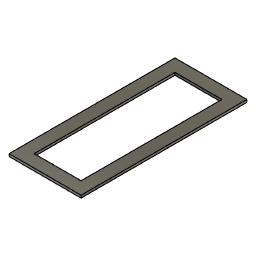
KOGUMA-CHAN (Autodesk Fusion 360 archive; units mm, degrees)
design "1次スカート"
Autodesk Fusion 360 part; units mm, degrees
(part 1 of 2)
sketch "スケッチ1" plane through (0, 0, 0) normal (0, 0, 1) x (1, 0, 0)
  line L0 (-50, 50) -> (-27, 50)
  line L1 (-27, 50) -> (-27, -3)
  line L2 (-27, -3) -> (-50, -3)
  line L3 (-50, -3) -> (-50, 50)
  dimension "d1" = 23
  dimension "d2" = 53
  constraint horizontal L0
  constraint vertical L1
  constraint horizontal L2
  constraint vertical L3
  measures "d1" distance of L0.start L0.end
  measures "d2" distance of L0.start L2.end
sketch "スケッチ2" plane through (0, 0, 0) normal (0, 0, 1) x (1, 0, 0)
extrude "押し出し1" add sketch "スケッチ1" along normal blind 0.8
sketch "スケッチ4" plane through (0, 0, 0.8) normal (0, 0, 1) x (-1, 0, 0)
  line L0 (50, 3) -> (27, 3)
  line L1 (27, 3) -> (27, -50)
  line L2 (27, -50) -> (50, -50)
  line L3 (50, -50) -> (50, 3)
  line L4 (27, 3) -> (50, -50)
  line L5 (27, -50) -> (50, 3)
  line L6 (46, -1) -> (31, -1)
  line L7 (31, -1) -> (31, -46)
  line L8 (31, -46) -> (46, -46)
  line L9 (46, -46) -> (46, -1)
  line L10 (46, -1) -> (31, -46) construction
  line L11 (31, -1) -> (46, -46) construction
  point P0 (38.5, -23.5)
  dimension "d9" = 15
  dimension "d10" = 45
  constraint coincident L0.end L1.start
  constraint coincident L2.end L3.start
  constraint coincident L1.end L2.start
  constraint coincident L0.start L3.end
  constraint horizontal L6
  constraint perpendicular L6 L7
  constraint parallel L6 L8
  constraint parallel L7 L9
  constraint coincident L10 P0
  constraint coincident L11 P0
  constraint midpoint L5 P0
  measures "d9" distance of L7.end L8.end
  measures "d10" distance of L6.end L7.end
extrude "押し出し3" cut sketch "スケッチ4" against normal blind 6 contours L4 L5 L9 | L4 L5 L6 L7 L9 | L4 L5 L7 | L4 L5 L7 L8 L9
sketch "スケッチ3" plane through (0, 0, 0.8) normal (0, 0, 1) x (-1, 0, 0)
  line L0 (50, 3) -> (27, 3)
  line L1 (27, 3) -> (27, -50)
  line L2 (27, -50) -> (50, -50)
  line L3 (50, -50) -> (50, 3)
  line L4 (50, 3) -> (27, -50)
  line L5 (50, -50) -> (27, 3)
  line L6 (26, -53.5) -> (51, -53.5)
  line L7 (51, -53.5) -> (51, 6.5)
  line L8 (51, 6.5) -> (26, 6.5)
  line L9 (26, 6.5) -> (26, -53.5)
  line L10 (26, -53.5) -> (51, 6.5) construction
  line L11 (51, -53.5) -> (26, 6.5) construction
  line L12 (31, -1) -> (46, -1)
  line L13 (46, -1) -> (46, -46)
  line L14 (46, -46) -> (31, -46)
  line L15 (31, -46) -> (31, -1)
  point P0 (38.5, -23.5)
  dimension "d5" = 25
  dimension "d6" = 60
  constraint coincident L0.start L3.end
  constraint coincident L1.end L2.start
  constraint coincident L2.end L3.start
  constraint coincident L0.end L1.start
  constraint horizontal L6
  constraint perpendicular L6 L7
  constraint parallel L6 L8
  constraint parallel L7 L9
  constraint coincident L10 P0
  constraint coincident L11 P0
  constraint midpoint L5 P0
  measures "d5" distance of L7.end L8.end
  measures "d6" distance of L6.end L7.end
extrude "押し出し2" [rolled back] along distance -1 taper angle 0

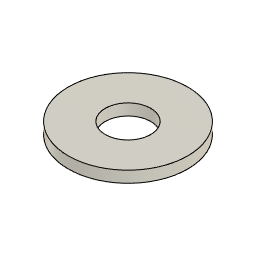
design "歯車M0.3T70"
Autodesk Fusion 360 part; units mm, degrees
sketch "スケッチ1" plane through (0, 0, 0) normal (0, 0, 1) x (1, 0, 0)
  circle A0 centre (0, 0) radius 10.5
  circle A1 centre (0, 0) radius 4
  dimension "d1" = 21
  dimension "d2" = 8
  constraint coincident A0.centre A1.centre
  measures "d1" diameter of A0
  measures "d2" diameter of A1
extrude "押し出し1" add sketch "スケッチ1" along normal blind 2

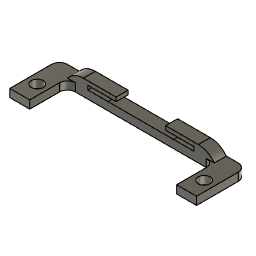
design "モータマウントバック"
Autodesk Fusion 360 part; units mm, degrees
sketch "スケッチ1" plane through (0, 0, 0) normal (0, 0, 1) x (1, 0, 0)
  line L0 (0, 0) -> (-46.8, 0)
  line L1 (-46.8, 0) -> (-46.8, 3)
  line L2 (-46.8, 3) -> (0, 3)
  line L3 (0, 3) -> (0, 0)
  line L4 (-46.8, 3) -> (-23.4, 3)
  line L5 (-46.8, 3) -> (-23.4, 3)
  line L6 (-23.4, 3) -> (-23.4, 0)
  line L7 (0, 0) -> (-5, 0)
  line L8 (-5, 0) -> (-5, -9.445)
  line L9 (-5, -9.445) -> (0, -9.445)
  line L10 (0, -9.445) -> (0, 0)
  line L11 (-5, -9.445) -> (-2.5, -9.445)
  line L12 (-2.5, -9.445) -> (-2.5, -5.045)
  circle A0 centre (-2.5, -5.045) radius 1.5
  line L13 (-41.8, 0) -> (-41.8, -9.445)
  line L14 (-46.8, -9.445) -> (-46.8, 0)
  circle A1 centre (-44.3, -5.045) radius 1.5
  line L15 (-41.8, -9.445) -> (-46.8, -9.445)
  dimension "d1" = 46.8
  dimension "d2" = 3
  dimension "d3" = 5
  dimension "d4" = 9.445
  dimension "d5" = 4.4
  dimension "d6" = 3
  constraint horizontal L0
  constraint vertical L1
  constraint horizontal L2
  constraint vertical L3
  constraint coincident L0.start L3.end
  constraint midpoint L2 L4.end
  constraint midpoint L0 L6.end
  constraint horizontal L7
  constraint vertical L8
  constraint horizontal L9
  constraint vertical L10
  constraint midpoint L9 L11.end
  constraint perpendicular L9 L12
  constraint coincident L12.end A0.centre
  constraint symmetric L6 L0.start L0.end
  constraint symmetric L6 L7.end L13.start
  constraint symmetric L6 L8.end L13.end
  constraint symmetric L6 L9.end L14.start
  constraint symmetric L6 A0 A1
  measures "d1" distance of L0.start L0.end
  measures "d2" distance of L0 L2
  measures "d3" distance of L0.start L7.end
  measures "d4" distance of L0.start L9.end
  measures "d5" distance of L11.end L12.end
  measures "d6" diameter of A0
extrude "押し出し1" add sketch "スケッチ1" along normal blind 2
fillet "フィレット1" radius 2 4 edges at (-41.8, 0, 1) (-5, 0, 1) (0, 3, 1) (-46.8, 3, 1)
sketch "スケッチ2" plane through (0, 0, 2) normal (0, 0, 1) x (-1, 0, 0)
  arc A0 (44.8, -3) -> (46.8, -1) centre (44.8, -1) ccw
  line L0 (46.8, -1) -> (46.8, 9.445)
  line L1 (46.8, 9.445) -> (41.8, 9.445)
  line L2 (41.8, 9.445) -> (41.8, 2)
  arc A1 (39.8, 0) -> (41.8, 2) centre (39.8, 2) ccw
  line L3 (39.8, 0) -> (7, 0)
  arc A2 (5, 2) -> (7, 0) centre (7, 2) ccw
  line L4 (5, 2) -> (5, 9.445)
  line L5 (5, 9.445) -> (0, 9.445)
  line L6 (0, 9.445) -> (0, -1)
  arc A3 (0, -1) -> (2, -3) centre (2, -1) ccw
  line L7 (2, -3) -> (44.8, -3)
  circle A4 centre (44.3, 5.045) radius 1.5
  circle A5 centre (2.5, 5.045) radius 1.5
  line L8 (41.8, 9.445) -> (41.8, -1)
  line L9 (41.8, -1) -> (41.8, 0)
  line L10 (41.8, 0) -> (3.6393, 0)
  line L11 (3.6393, 0) -> (5, 0)
  line L12 (5, 0) -> (41.8, 0)
  line L13 (41.8, 0) -> (41.8, -3)
  line L14 (41.8, -3) -> (5, -3)
  line L15 (5, -3) -> (5, 0)
  constraint coincident L1.end L2.start
  constraint perpendicular L1 L8
  constraint coincident L8 L9.end
  constraint perpendicular L8 L10
  constraint coincident L10 L11.end
  constraint horizontal L12
  constraint vertical L13
  constraint horizontal L14
  constraint vertical L15
  constraint coincident L7 L13.end
extrude "押し出し2" add sketch "スケッチ2" along normal blind 2 contours L3 L7 L8 L9 L10 L12 L13 L14 L15
sketch "スケッチ3" plane through (0, 0, 0) normal (0, -1, 0) x (1, 0, 0)
  line L0 (-7, 0) -> (-7, 2)
  line L1 (-7, 2) -> (-5, 2)
  line L2 (-5, 2) -> (-5, 4)
  line L3 (-5, 4) -> (-41.8, 4)
  line L4 (-41.8, 4) -> (-41.8, 2)
  line L5 (-41.8, 2) -> (-39.8, 2)
  line L6 (-39.8, 2) -> (-39.8, 0)
  line L7 (-39.8, 0) -> (-7, 0)
  line L8 (-39.8, 2) -> (-7, 2)
  line L9 (-39.8, 2) -> (-23.4, 2)
  line L10 (-39.8, 2) -> (-31.6, 2)
  line L11 (-31.6, 2) -> (-31.6, 4)
  line L12 (-7, 2) -> (-23.4, 2)
  line L13 (-7, 2) -> (-15.2, 2)
  line L14 (-15.2, 2) -> (-15.2, 4)
  line L15 (-31.6, 4) -> (-15.2, 4)
  line L16 (-15.2, 4) -> (-15.2, 2)
  line L17 (-15.2, 2) -> (-31.6, 2)
  line L18 (-31.6, 2) -> (-31.6, 4)
  constraint coincident L5.end L6.start
  constraint coincident L0.end L1.start
  constraint midpoint L8 L9.end
  constraint midpoint L9 L10.end
  constraint coincident L3 L11.end
  constraint perpendicular L3 L11
  constraint midpoint L12 L13.end
  constraint coincident L3 L14.end
  constraint perpendicular L3 L14
  constraint horizontal L15
  constraint vertical L16
  constraint horizontal L17
  constraint vertical L18
extrude "押し出し3" cut sketch "スケッチ3" against normal blind 3 contours L3 L8 L9 L11 L12 L14 L15 L16 L17 L18
sketch "スケッチ4" plane through (0, 0, 0) normal (0, -1, 0) x (1, 0, 0)
  line L0 (-31.6, 2) -> (-31.6, 4)
  line L1 (-31.6, 4) -> (-41.8, 4)
  line L2 (-41.8, 4) -> (-41.8, 2)
  line L3 (-41.8, 2) -> (-39.8, 2)
  line L4 (-39.8, 2) -> (-39.8, 0)
  line L5 (-39.8, 0) -> (-7, 0)
  line L6 (-7, 0) -> (-7, 2)
  line L7 (-7, 2) -> (-5, 2)
  line L8 (-5, 2) -> (-5, 4)
  line L9 (-5, 4) -> (-15.2, 4)
  line L10 (-15.2, 4) -> (-15.2, 2)
  line L11 (-15.2, 2) -> (-31.6, 2)
  line L12 (-31.6, 4) -> (-31.6, 3)
  line L13 (-31.6, 3) -> (-36.7, 3)
  line L14 (-36.7, 3) -> (-36.7, 2)
  line L15 (-36.7, 2) -> (-31.6, 2)
  line L16 (-15.2, 4) -> (-15.2, 3)
  line L17 (-15.2, 3) -> (-10.1, 3)
  line L18 (-10.1, 3) -> (-10.1, 2)
  line L19 (-10.1, 2) -> (-15.2, 2)
  line L20 (-15.2, 3) -> (-15.2, 2)
  line L21 (-31.6, 3) -> (-31.6, 2)
  constraint coincident L0.end L1.start
  constraint midpoint L0 L12.end
  constraint perpendicular L12 L13
  constraint perpendicular L1 L14
  constraint coincident L0.start L11.end
  constraint coincident L9.end L10.start
  constraint midpoint L10 L16.end
  constraint perpendicular L10 L17
  constraint perpendicular L17 L18
  constraint coincident L10.end L11.start
extrude "押し出し4" cut sketch "スケッチ4" against normal blind 4 contours L0 L13 L14 L15 L21 | L10 L17 L18 L19 L20
fillet "フィレット2" radius 5 2 edges at (-41.8, 1.5, 4) (-5, 1.5, 4)
extrude "押し出し5" add 1 faces at (-31.6, 1, 3.3333) along direction (1, 0, 0) blind 2
extrude "押し出し6" add 1 faces at (-15.2, 1, 3.3333) along direction (-1, 0, 0) blind 2
equation "d5 = 2.9 mm + 1.5 mm"

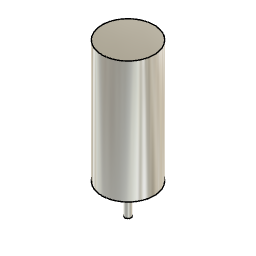
design "吸引モータ"
Autodesk Fusion 360 part; units mm, degrees
sketch "スケッチ1" plane through (0, 0, 0) normal (0, 0, 1) x (1, 0, 0)
  circle A0 centre (0, 0) radius 4.25
  dimension "d1" = 8.5
  constraint coincident A0.centre origin
  measures "d1" diameter of A0
extrude "押し出し1" add sketch "スケッチ1" along normal blind 20
sketch "スケッチ2" plane through (0, 0, 0) normal (0, 0, -1) x (1, 0, 0)
  circle A0 centre (0, 0) radius 4.25
  circle A1 centre (0, 0) radius 0.5
  dimension "d4" = 1
  constraint coincident A0.centre A1.centre
  measures "d4" diameter of A1
extrude "押し出し2" add sketch "スケッチ2" along normal blind 5 contours A1

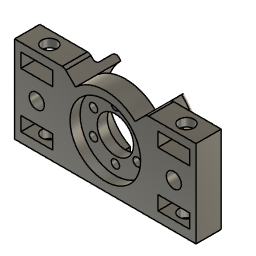
design "モーターマウント"
Autodesk Fusion 360 part; units mm, degrees
sketch "スケッチ1" plane through (0, 0, 0) normal (0, 1, 0) x (1, 0, 0)
  circle A0 centre (0, 0) radius 8.6
  line L0 (57.1333, 8.5) -> (67.1333, 8.5) construction
  circle A1 centre (0, 0) radius 3.6
  circle A2 centre (-13.6, 0) radius 10.5 construction
  circle A3 centre (13.6, 0) radius 10.5 construction
  circle A4 centre (0, 0) radius 5
  circle A5 centre (-0.0024, -5) radius 0.825
  circle A6 centre (4.3289, -2.502) radius 0.825
  circle A7 centre (4.3313, 2.498) radius 0.825
  circle A8 centre (0.0024, 5) radius 0.825
  circle A9 centre (-4.3289, 2.502) radius 0.825
  circle A10 centre (-4.3313, -2.498) radius 0.825
  circle A11 centre (-13.6, 0) radius 12.25 construction
  circle A12 centre (-13.6, 0) radius 1.5
  circle A13 centre (13.6, 0) radius 1.5
  line L1 (-13.6, 0) -> (-13.6, 12.25)
  line L2 (-13.6, 12.25) -> (-3.6, 12.25)
  line L3 (-3.6, 12.25) -> (-3.6, 9.75)
  line L4 (-3.6, 9.75) -> (-3.6, 8.75)
  line L5 (-3.6, 8.75) -> (27, 8.75)
  line L6 (0, 0) -> (0, 8.75)
  line L7 (0, 8.75) -> (18, 8.75)
  line L8 (18, 8.75) -> (18, -6.25)
  line L9 (18, -6.25) -> (0, -6.25)
  line L10 (0, -6.25) -> (0, 8.75)
  line L11 (-18, -6.25) -> (0, -6.25)
  line L12 (-18, 8.75) -> (-18, -6.25)
  line L13 (0, 8.75) -> (-18, 8.75)
  line L14 (18, -6.25) -> (-18, -6.25)
  line L15 (-18, -6.25) -> (-18, -8.4837)
  line L16 (-18, -8.4837) -> (18, -8.4837)
  line L17 (18, -8.4837) -> (18, -6.25)
  line L18 (18, -8.4837) -> (9, -8.4837)
  line L19 (18, -8.4837) -> (8, -8.4837)
  line L20 (5.9074, -6.25) -> (8.1411, -8.4837)
  line L21 (5.9074, -6.25) -> (8.9428, -6.25) construction
  line L22 (-5.9074, -6.25) -> (-8.1574, -8.5)
  dimension "d1" = 17.2
  dimension "d2" = 8.5
  dimension "d3" = 7.2
  dimension "d4" = 21
  dimension "d5" = 13.6
  dimension "d7" = 21
  dimension "d8" = 13.6
  dimension "d9" = 8.5
  dimension "d10" = 8.5
  dimension "d16" = 10
  dimension "d17" = 1.65
  dimension "d19" = 360
  dimension "d20" = 24.5
  dimension "d21" = 3
  dimension "d22" = 3
  dimension "d25" = 2.5
  dimension "d26" = 1
  dimension "d27" = 18
  dimension "d28" = 15
  dimension "d48" = 45
  dimension "d49" = 90
  dimension "d50" = 3.182
  constraint coincident A0.centre A1.centre
  constraint horizontal L0
  constraint concentric A0 A1
  constraint concentric A0 A4
  constraint coincident A4 A5.centre
  constraint concentric A2 A11
  constraint concentric A2 A12
  constraint concentric A3 A13
  constraint coincident A2.centre A11.centre
  constraint coincident A11 L1.end
  constraint vertical L1
  constraint tangent A11 L2
  constraint equal L0 L2
  constraint perpendicular L2 L3
  constraint parallel L3 L4
  constraint perpendicular L4 L5
  constraint coincident L5 L6.end
  constraint perpendicular L5 L6
  constraint horizontal L7
  constraint vertical L8
  constraint horizontal L9
  constraint vertical L10
  constraint symmetric L6.end L10 L7.start
  constraint symmetric L7.end L10 L12.start
  constraint symmetric L8.end L10 L11.start
  constraint symmetric L9.end L10 L11.end
  constraint horizontal L14
  constraint vertical L15
  constraint horizontal L16
  constraint vertical L17
  constraint coincident L16 L18.end
  constraint perpendicular L17 L18
  constraint coincident L16 L19.end
  constraint horizontal L21
  constraint coincident A0 L20.start
  constraint coincident L14 L20.start
  constraint coincident L16 L20.end
  constraint coincident A0 L22.start
  constraint coincident L14 L22.start
  measures "d1" diameter of A0
  measures "d2" distance of A0.centre L0
  measures "d3" diameter of A1
  measures "d4" diameter of A2
  measures "d5" distance of A0.centre A2.centre
  measures "d7" diameter of A3
  measures "d8" distance of A0.centre A3.centre
  measures "d9" distance of L0 A3.centre
  measures "d10" distance of L0 A2.centre
  measures "d16" diameter of A4
  measures "d17" diameter of A5
  measures "d20" diameter of A11
  measures "d21" diameter of A12
  measures "d22" diameter of A13
  measures "d25" distance of L2.end L3.end
  measures "d26" distance of L3.end L4.end
  measures "d27" distance of L6.end L7.end
  measures "d28" distance of L6.end L9.end
  measures "d48" angle of L20 L21
  measures "d49" angle of L20 L22
  measures "d50" distance of L22.start L22.end
extrude "押し出し1" add sketch "スケッチ1" against normal blind 5 contours A0 A4 A5 A6 A7 A8 L6 L9 L10 L14 | A0 L5 L6 L7 L8 L9 L10 L14 | A0 L9 L11 L14 L16 | L9 L14 L16 L17 L18 L19 L20 | A0 L16 | A0 A4 A5 A8 A9 A10 L6 L10 L11 L14 | A0 L5 L6 L10 L11 L12 L13 L14 | L11 L14 L15 L16 L22 | A1 A4 A5 A8 A9 A10 L6 L10 | A1 A4 A5 A6 A7 A8 L6 L10
sketch "スケッチ2" plane through (0, 0, -8.75) normal (0, 0, -1) x (1, 0, 0)
  line L0 (-18, 0) -> (18, 0)
  line L1 (18, 0) -> (18, 5)
  line L2 (18, 5) -> (-18, 5)
  line L3 (-18, 5) -> (-18, 0)
  line L4 (-18, 5) -> (-13.6, 5)
  line L5 (-13.6, 5) -> (-13.6, 0)
  line L6 (-13.6, 5) -> (-13.6, 2.5)
  line L7 (-18, 2.5) -> (-13.6, 2.5)
  circle A0 centre (-13.6, 2.5) radius 1.05
  line L8 (0, 0) -> (0, 5)
  circle A1 centre (13.6, 2.5) radius 1.05
  dimension "d31" = 4.4
  dimension "d33" = 2.1
  constraint coincident L2.end L3.start
  constraint perpendicular L3 L4
  constraint coincident L0 L5.end
  constraint perpendicular L0 L5
  constraint midpoint L5 L6.end
  constraint midpoint L3 L7.start
  constraint coincident L6.end L7.end
  constraint coincident L8.start origin
  constraint midpoint L2 L8.end
  constraint symmetric A0 L8 A1
  measures "d31" distance of L2.end L4.end
  measures "d33" diameter of A0
hole "穴1" at (-13.6, -2.5, -8.75) at (13.6, -2.5, -8.75) direction (0, 0, 1) diameter 3 depth 4 tip angle 180
sketch "スケッチ3" plane through (0, -5, 0) normal (0, -1, 0) x (1, 0, 0)
  circle A0 centre (13.6, 0) radius 1.5
  circle A1 centre (-0.0024, 5) radius 0.825
  circle A2 centre (4.3289, 2.502) radius 0.825
  circle A3 centre (4.3313, -2.498) radius 0.825
  circle A4 centre (-4.3313, 2.498) radius 0.825
  circle A5 centre (0.0024, -5) radius 0.825
  circle A6 centre (-4.3289, -2.502) radius 0.825
  circle A7 centre (-13.6, 0) radius 1.5
  line L0 (-18, -8.75) -> (18, -8.75)
  line L1 (18, -8.75) -> (18, 8.4837)
  line L2 (-18, 8.4837) -> (-18, -8.75)
  circle A8 centre (0, 0) radius 7
  line L3 (-8.1411, 8.4837) -> (-18, 8.4837)
  arc A9 (5.9074, 6.25) -> (-5.9074, 6.25) centre (0, 0) ccw
  line L4 (-5.9074, 6.25) -> (-8.1411, 8.4837)
  line L5 (18, 8.4837) -> (8.1411, 8.4837)
  line L6 (8.1411, 8.4837) -> (5.9074, 6.25)
  circle A10 centre (0, 0) radius 3.6
  dimension "d37" = 14
  constraint coincident A8.centre A9.centre
  measures "d37" diameter of A8
extrude "押し出し2" cut sketch "スケッチ3" against normal blind 2 contours A8 | A10
sketch "スケッチ4" plane through (0, 0, 0) normal (0, 1, 0) x (-1, 0, 0)
  circle A0 centre (-13.6, 0) radius 1.5
  circle A1 centre (0.0024, 5) radius 0.825
  circle A2 centre (-4.3289, 2.502) radius 0.825
  circle A3 centre (-4.3313, -2.498) radius 0.825
  circle A4 centre (4.3313, 2.498) radius 0.825
  circle A5 centre (-0.0024, -5) radius 0.825
  circle A6 centre (4.3289, -2.502) radius 0.825
  circle A7 centre (13.6, 0) radius 1.5
  line L0 (-18, -8.75) -> (18, -8.75)
  line L1 (18, -8.75) -> (18, 8.4837)
  line L2 (-18, 8.4837) -> (-18, -8.75)
  circle A8 centre (0, 0) radius 8.6
  line L3 (-8.1411, 8.4837) -> (-18, 8.4837)
  arc A9 (5.9074, 6.25) -> (-5.9074, 6.25) centre (0, 0) ccw
  line L4 (-5.9074, 6.25) -> (-8.1411, 8.4837)
  line L5 (18, 8.4837) -> (8.1411, 8.4837)
  line L6 (8.1411, 8.4837) -> (5.9074, 6.25)
  circle A10 centre (0, 0) radius 3.6
  dimension "d85" = 17.2
  measures "d85" diameter of A8
extrude "押し出し3" cut sketch "スケッチ4" against normal blind 1 contours A8 A9 | A10
sketch "スケッチ5" plane through (0, 0, 0) normal (0, 1, 0) x (-1, 0, 0)
  line L0 (-18, 8.4837) -> (-18, -8.75)
  line L1 (-18, -8.75) -> (18, -8.75)
  line L2 (18, -8.75) -> (18, 8.4837)
  circle A0 centre (13.6, 0) radius 1.5
  circle A1 centre (-13.6, 0) radius 1.5
  line L3 (-13.6, 0) -> (-13.6, 3.3255)
  line L4 (-13.6, 0) -> (-10.72, 1.6628)
  line L5 (-13.6, 0) -> (-9.9931, 0) construction
  line L6 (-13.6, 3.3255) -> (-10.72, 1.6628)
  line L7 (-16.48, 1.6628) -> (-13.6, 3.3255)
  line L8 (-16.48, -1.6627) -> (-16.48, 1.6627)
  line L9 (-13.6, -3.3255) -> (-16.48, -1.6628)
  line L10 (-10.72, -1.6628) -> (-13.6, -3.3255)
  line L11 (-10.72, 1.6627) -> (-10.72, -1.6628)
  line L12 (0, 0) -> (0, 5)
  line L13 (13.6, 3.3255) -> (10.72, 1.6628)
  line L14 (10.72, 1.6627) -> (10.72, -1.6628)
  line L15 (10.72, -1.6628) -> (13.6, -3.3255)
  line L16 (13.6, -3.3255) -> (16.48, -1.6628)
  line L17 (16.48, -1.6627) -> (16.48, 1.6627)
  line L18 (16.48, 1.6628) -> (13.6, 3.3255)
  line L19 (18, 8.4837) -> (8.1411, 8.4837)
  line L20 (-8.1411, 8.4837) -> (-18, 8.4837)
  line L21 (-5.9074, 6.25) -> (-8.1411, 8.4837)
  line L22 (8.1411, 8.4837) -> (5.9074, 6.25)
  arc A2 (-5.9074, 6.25) -> (5.9074, 6.25) centre (0, 0) ccw
  dimension "d42" = 3.3255
  dimension "d43" = 30
  dimension "d45" = 360
  constraint coincident A1.centre L3.start
  constraint vertical L3
  constraint horizontal L5
  constraint equal L3 L4
  constraint vertical L12
  constraint symmetric L3.end L12 L13.start
  constraint symmetric L4.end L12 L13.end
  constraint symmetric L7.start L12 L18.start
  constraint symmetric L8.start L12 L17.start
  constraint symmetric L8.end L12 L17.end
  constraint symmetric L9.start L12 L15.end
  constraint symmetric L9.end L12 L16.end
  constraint symmetric L10.start L12 L14.end
  constraint symmetric L11.start L12 L14.start
  measures "d42" distance of A1.centre L3.end
  measures "d43" angle of L4 L5
extrude "押し出し4" cut sketch "スケッチ5" against normal blind 2.5 contours A1 L3 L4 L7 L8 L9 L10 L11 | A1 L3 L4 L6 | L13 L14 L15 L16 L17 L18
fillet "フィレット1" radius 1 1 edges at (8.1411, -2.5, 8.4837)
fillet "フィレット2" radius 1 1 edges at (-8.1411, -2.5, 8.4837)
sketch "スケッチ6" plane through (0, 0, 0) normal (0, 1, 0) x (1, 0, 0)
sketch "スケッチ7" plane through (0, 0, -8.75) normal (0, 0, -1) x (1, 0, 0)
  circle A0 centre (-13.6, 2.5) radius 1.5
  circle A1 centre (13.6, 2.5) radius 1.5
  line L0 (-18, 0) -> (18, 0)
  line L1 (18, 0) -> (18, 5)
  line L2 (18, 5) -> (-18, 5)
  line L3 (-18, 5) -> (-18, 0)
  line L4 (18, 2.5) -> (9, 2.5)
  line L5 (9, 2.5) -> (9, 2)
  line L6 (9, 2) -> (4, 2)
  line L7 (4, 2) -> (4, 3)
  line L8 (4, 3) -> (9, 3)
  line L9 (9, 3) -> (9, 2.5)
  line L10 (18, 2.5) -> (13.6, 2.5)
  line L11 (18, 2.5) -> (15.8, 2.5)
  line L12 (15.8, 2.5) -> (15.8, 4)
  line L13 (15.8, 4) -> (16.8, 4)
  line L14 (16.8, 4) -> (16.8, 1)
  line L15 (16.8, 1) -> (15.8, 1)
  line L16 (15.8, 1) -> (15.8, 2.5)
  line L17 (0, 0) -> (0, 5)
  line L18 (-16.8, 1) -> (-15.8, 1)
  line L19 (-16.8, 4) -> (-16.8, 1)
  line L20 (-15.8, 1) -> (-15.8, 2.5)
  line L21 (-15.8, 2.5) -> (-15.8, 4)
  line L22 (-15.8, 4) -> (-16.8, 4)
  line L23 (-9, 2.5) -> (-9, 2)
  line L24 (-9, 3) -> (-9, 2.5)
  line L25 (-4, 3) -> (-9, 3)
  line L26 (-9, 2) -> (-4, 2)
  line L27 (-4, 2) -> (-4, 3)
  dimension "d55" = 1
  dimension "d56" = 90
  dimension "d57" = 3
  dimension "d58" = 1
  dimension "d59" = 0.5
  dimension "d60" = 0.5
  dimension "d61" = 5
  constraint midpoint L1 L4.start
  constraint perpendicular L1 L4
  constraint perpendicular L4 L5
  constraint perpendicular L5 L6
  constraint perpendicular L6 L7
  constraint perpendicular L7 L8
  constraint perpendicular L4 L9
  constraint coincident A1.centre L10.end
  constraint midpoint L10 L11.end
  constraint perpendicular L4 L12
  constraint perpendicular L11 L14
  constraint perpendicular L14 L15
  constraint coincident L17.start origin
  constraint midpoint L2 L17.end
  constraint symmetric L4.end L17 L23.start
  constraint symmetric L5.end L17 L23.end
  constraint symmetric L6.end L17 L26.end
  constraint symmetric L7.end L17 L25.start
  constraint symmetric L8.end L17 L24.start
  constraint symmetric L11.end L17 L20.end
  constraint symmetric L12.end L17 L21.end
  constraint symmetric L13.end L17 L19.start
  constraint symmetric L14.end L17 L18.start
  constraint symmetric L15.end L17 L18.end
  measures "d55" distance of L12.end L13.end
  measures "d56" angle of L12 L13
  measures "d57" distance of L13.end L14.end
  measures "d58" distance of L14.end L15.end
  measures "d59" distance of L4.end L5.end
  measures "d60" distance of L4.end L8.end
  measures "d61" distance of L7.end L8.end
sketch "スケッチ8" plane through (0, 0, 0) normal (0, 1, 0) x (-1, 0, 0)
  line L0 (-16.48, 1.6627) -> (-13.6, 3.3255)
  line L1 (-13.6, 3.3255) -> (-10.72, 1.6627)
  line L2 (-10.72, 1.6627) -> (-10.72, -1.6628)
  line L3 (-10.72, -1.6628) -> (-13.6, -3.3255)
  line L4 (-13.6, -3.3255) -> (-16.48, -1.6628)
  line L5 (-16.48, -1.6628) -> (-16.48, 1.6627)
  line L6 (10.72, 1.6627) -> (13.6, 3.3255)
  line L7 (13.6, 3.3255) -> (16.48, 1.6628)
  line L8 (16.48, 1.6628) -> (16.48, -1.6627)
  line L9 (16.48, -1.6627) -> (13.6, -3.3255)
  line L10 (13.6, -3.3255) -> (10.72, -1.6628)
  line L11 (10.72, -1.6628) -> (10.72, 1.6627)
  arc A0 (8.5553, 8.4837) -> (7.8482, 8.1908) centre (8.5553, 7.4837) ccw
  line L12 (7.8482, 8.1908) -> (5.9074, 6.25)
  line L13 (-5.9074, 6.25) -> (-7.8482, 8.1908)
  arc A1 (-7.8482, 8.1908) -> (-8.5553, 8.4837) centre (-8.5553, 7.4837) ccw
  line L14 (-8.5553, 8.4837) -> (-18, 8.4837)
  line L15 (-18, 8.4837) -> (-18, -8.75)
  line L16 (-18, -8.75) -> (18, -8.75)
  line L17 (18, -8.75) -> (18, 8.4837)
  line L18 (18, 8.4837) -> (8.5553, 8.4837)
  arc A2 (-5.9074, 6.25) -> (5.9074, 6.25) centre (0, 0) ccw
sketch "スケッチ9" plane through (0, -5, 0) normal (0, -1, 0) x (1, 0, 0)
  arc A0 (-7.8482, 8.1908) -> (-8.5553, 8.4837) centre (-8.5553, 7.4837) ccw
  line L0 (-8.5553, 8.4837) -> (-18, 8.4837)
  line L1 (-18, 8.4837) -> (-18, -8.75)
  line L2 (-18, -8.75) -> (18, -8.75)
  line L3 (18, -8.75) -> (18, 8.4837)
  line L4 (18, 8.4837) -> (8.5553, 8.4837)
  arc A1 (8.5553, 8.4837) -> (7.8482, 8.1908) centre (8.5553, 7.4837) ccw
  line L5 (7.8482, 8.1908) -> (5.9074, 6.25)
  arc A2 (5.9074, 6.25) -> (-5.9074, 6.25) centre (0, 0) ccw
  line L6 (-5.9074, 6.25) -> (-7.8482, 8.1908)
  circle A3 centre (0, 0) radius 7
  circle A4 centre (13.6, 0) radius 1.5
  circle A5 centre (-13.6, 0) radius 1.5
  line L7 (-13.6, 0) -> (-13.6, -8.75)
  line L8 (-13.6, -8.75) -> (-13.6, -5.75)
  line L9 (-13.6, -5.75) -> (-13.6, -6.85)
  line L10 (-13.6, -6.85) -> (-10.45, -6.85)
  line L11 (-10.45, -6.85) -> (-16.75, -6.85)
  line L12 (-16.75, -6.85) -> (-16.75, -4.05)
  line L13 (-16.75, -4.05) -> (-10.45, -4.05)
  line L14 (-10.45, -4.05) -> (-10.45, -6.85)
  line L15 (-13.6, 0) -> (-12.1, 0)
  line L16 (-10.45, 4.05) -> (-10.45, 6.85)
  line L17 (-16.75, 4.05) -> (-10.45, 4.05)
  line L18 (-16.75, 6.85) -> (-16.75, 4.05)
  line L19 (-10.45, 6.85) -> (-16.75, 6.85)
  line L20 (0, 0) -> (0, -1.3503)
  line L21 (16.75, 4.05) -> (10.45, 4.05)
  line L22 (16.75, 6.85) -> (16.75, 4.05)
  line L23 (10.45, 6.85) -> (16.75, 6.85)
  line L24 (10.45, 4.05) -> (10.45, 6.85)
  line L25 (16.75, -4.05) -> (10.45, -4.05)
  line L26 (10.45, -4.05) -> (10.45, -6.85)
  line L27 (16.75, -6.85) -> (16.75, -4.05)
  line L28 (10.45, -6.85) -> (16.75, -6.85)
  dimension "d64" = 3
  dimension "d65" = 1.1
  dimension "d66" = 3.15
  dimension "d67" = 6.3
  dimension "d68" = 2.8
  constraint coincident A5.centre L7.start
  constraint coincident L2 L7.end
  constraint perpendicular L2 L7
  constraint perpendicular L2 L8
  constraint parallel L7 L9
  constraint perpendicular L9 L10
  constraint horizontal L11
  constraint vertical L12
  constraint horizontal L13
  constraint vertical L14
  constraint coincident A5 L15.end
  constraint perpendicular L7 L15
  constraint symmetric L10.end L15 L16.end
  constraint symmetric L11.end L15 L18.start
  constraint symmetric L12.end L15 L17.start
  constraint symmetric L13.end L15 L16.start
  constraint coincident A2.centre A3.centre
  constraint vertical L20
  constraint symmetric L10.end L20 L26.end
  constraint symmetric L11.end L20 L27.start
  constraint symmetric L12.end L20 L25.start
  constraint symmetric L13.end L20 L25.end
  constraint symmetric L16.start L20 L21.end
  constraint symmetric L16.end L20 L23.start
  constraint symmetric L17.start L20 L21.start
  constraint symmetric L18.start L20 L22.start
  measures "d64" distance of L7.end L8.end
  measures "d65" distance of L8.end L9.end
  measures "d66" distance of L9.end L10.end
  measures "d67" distance of L10.end L11.end
  measures "d68" distance of L10.end L13.end
sketch "スケッチ10" plane through (0, -5, 0) normal (0, -1, 0) x (1, 0, 0)
extrude "押し出し6" cut sketch "スケッチ9" against normal blind 6.5 contours L7 L8 L9 L10 L11 L13 L14 | L7 L8 L9 L11 L12 L13 | L16 L17 L18 L19 | L21 L22 L23 L24 | L25 L26 L27 L28
sketch "スケッチ11" plane through (0, 0, 8.4837) normal (0, 0, 1) x (-1, 0, 0)
  line L0 (8.5553, 5) -> (8.5553, 0)
  line L1 (8.5553, 0) -> (18, 0)
  line L2 (18, 0) -> (18, 5)
  line L3 (18, 5) -> (8.5553, 5)
  line L4 (18, 5) -> (18, 2.5)
  line L5 (18, 2.5) -> (13.6, 2.5)
  line L6 (0, 0) -> (0, 5)
  line L7 (-18, 2.5) -> (-13.6, 2.5)
  dimension "d71" = 4.4
  constraint coincident L2.end L3.start
  constraint midpoint L2 L4.end
  constraint perpendicular L2 L5
  constraint coincident L6.start origin
  constraint vertical L6
  constraint symmetric L4.end L6 L7.start
  constraint symmetric L5.end L6 L7.end
  measures "d71" distance of L4.end L5.end
hole "穴2" at (-13.6, -2.5, 8.4837) at (13.6, -2.5, 8.4837) direction (0, 0, -1) diameter 3 depth 3 tip angle 180
sketch "スケッチ12" plane through (0, 0, 0) normal (0, 1, 0) x (-1, 0, 0)
  line L0 (18, -8.75) -> (-18, -8.75)
  line L1 (-18, -8.75) -> (-18, 8.6)
  line L2 (-18, 8.6) -> (18, 8.6)
  line L3 (18, 8.6) -> (18, -8.75)
  circle A0 centre (0, 0) radius 8.6
  circle A1 centre (0, 0) radius 10
  line L4 (-5.9074, 6.25) -> (-964.7442, 965.0868)
  line L5 (-5.9074, 6.25) -> (1350.239, 6.25) construction
  line L6 (0, 0) -> (0, 1.2)
  line L7 (5.9074, 6.25) -> (964.7442, 965.0868)
  line L8 (-4.0393, -8.75) -> (-4.0393, -7.5924)
  line L9 (4.0393, -8.75) -> (4.0393, -7.5924)
  line L10 (-5.9074, 6.25) -> (-7.8482, 8.1908)
  dimension "d75" = 20
  dimension "d76" = 135
  dimension "d77" = 1356
  dimension "d84" = 17.2
  constraint horizontal L0
  constraint vertical L1
  constraint horizontal L2
  constraint vertical L3
  constraint coincident A0.centre A1.centre
  constraint tangent L2 A0
  constraint concentric A0 A1
  constraint horizontal L5
  constraint coincident A0 L4.start
  constraint vertical L6
  constraint symmetric L4.start L6 L7.start
  constraint symmetric L4.end L6 L7.end
  constraint coincident L0 L8.start
  constraint coincident A0 L8.end
  constraint perpendicular L0 L8
  constraint symmetric L6 L8.start L9.start
  constraint symmetric L6 L8.end L9.end
  constraint collinear L4 L10
  measures "d75" diameter of A1
  measures "d76" angle of L4 L5
  measures "d77" distance of L4.start L4.end
  measures "d84" diameter of A0
extrude "押し出し7" add sketch "スケッチ12" along normal blind 4 contours L0 A0 A1 L7 L9 | L0 A0 A1 L4 L8 L10
fillet "フィレット3" radius 0.75 2 edges at (-9.9183, 0, -1.2756) (9.9183, 0, -1.2756)
fillet "フィレット4" radius 0.75 2 edges at (9.9183, 4, -1.2756) (-9.9183, 4, -1.2756)
equation "d1 = 17 mm + 0.2 mm"
equation "d5 = ( 6 / 2 ) * 1 mm + ( 21 / 2 ) * 1 mm + 0.1 mm"
equation "d8 = ( 6 / 2 ) * 1 mm + ( 21 / 2 ) * 1 mm + 0.1 mm"
equation "d31 = 2.9 mm + 1.5 mm"
equation "d42 = ( ( 6.351 / 2 ) * 1 ) * 1 mm + 0.15 mm"
equation "d66 = 2.750 mm + 0.4 mm"
equation "d68 = 2.4 mm + 0.4 mm"
equation "d85 = 17.00 mm + 0.2 mm"

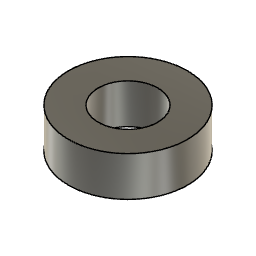
design "ベアリング（D６ｄ３）"
Autodesk Fusion 360 part; units mm, degrees
sketch "スケッチ1" plane through (0, 0, 0) normal (0, 0, 1) x (1, 0, 0)
  circle A0 centre (0, 0) radius 1.5
  circle A1 centre (0, 0) radius 3
  dimension "d1" = 3
  dimension "d2" = 6
  constraint coincident A0.centre A1.centre
  measures "d1" diameter of A0
  measures "d2" diameter of A1
extrude "押し出し1" add sketch "スケッチ1" along normal blind 2

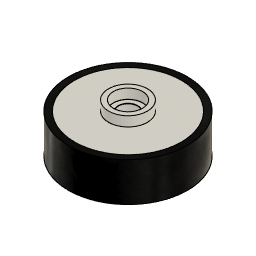
design "ホイール＆タイヤ（mini-zナロー2mm）"
Autodesk Fusion 360 part; units mm, degrees
sketch "スケッチ1" plane through (0, 0, 0) normal (0, 0, 1) x (1, 0, 0)
  circle A0 centre (0, 0) radius 11
  circle A1 centre (0, 0) radius 4
  circle A2 centre (0, 0) radius 3
  dimension "d1" = 22
  dimension "d4" = 8
  dimension "d5" = 6
  constraint coincident A0.centre A1.centre
  constraint concentric A0 A1
  measures "d1" diameter of A0
  measures "d4" diameter of A1
  measures "d5" diameter of A2
extrude "押し出し1" add sketch "スケッチ1" along normal blind 8 contours A0 | A1 makes body 1
sketch "スケッチ2" plane through (0, 0, 8) normal (0, 0, 1) x (-1, 0, 0)
  circle A0 centre (0, 0) radius 3
  circle A1 centre (0, 0) radius 11
  circle A2 centre (0, 0) radius 3
  circle A3 centre (0, 0) radius 4
  dimension "d6" = 8
  constraint coincident A0.centre A1.centre
  measures "d6" diameter of A3
extrude "押し出し2" add sketch "スケッチ2" along normal blind 2 contours A3 bodies 1
sketch "スケッチ3" plane through (0, 0, 8) normal (0, 0, 1) x (-1, 0, 0)
  circle A0 centre (0, 0) radius 4
  circle A1 centre (0, 0) radius 11
  circle A2 centre (0, 0) radius 3
  circle A3 centre (0, 0) radius 2
  dimension "d9" = 6
  dimension "d10" = 4
  constraint coincident A0.centre A1.centre
  constraint concentric A2 A3
  measures "d9" diameter of A2
  measures "d10" diameter of A3
extrude "押し出し3" add sketch "スケッチ3" against normal blind 0.1 bodies 1
sketch "スケッチ4" plane through (0, 0, 0) normal (0, 0, 1) x (1, 0, 0)
  circle A0 centre (0, 0) radius 11
  circle A1 centre (0, 0) radius 12.25
  dimension "d13" = 24.5
  constraint coincident A0.centre A1.centre
  constraint concentric A0 A1
  measures "d13" diameter of A1
extrude "押し出し1'" add sketch "スケッチ4" along normal blind 8 separate body makes body 2 in component "Component'"
component "Component'" placed x (1, 0, 0) y (0, 1, 0) z (0, 0, 1) at (0, 0, 0)

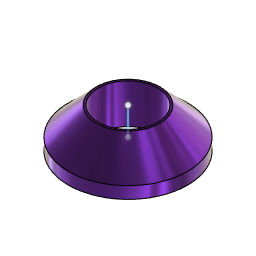
design "アルミテーパーM3"
Autodesk Fusion 360 part; units mm, degrees
sketch "スケッチ1" plane through (0, 0, 0) normal (0, 0, 1) x (1, 0, 0)
  circle A0 centre (0, 0) radius 1.5
  circle A1 centre (0, 0) radius 3
  dimension "d1" = 3
  dimension "d2" = 6
  constraint coincident A0.centre A1.centre
  measures "d1" diameter of A0
  measures "d2" diameter of A1
extrude "押し出し1" add sketch "スケッチ1" along normal blind 0.6
sketch "スケッチ2" plane through (0, 0, 0.6) normal (0, 0, 1) x (-1, 0, 0)
  circle A0 centre (0, 0) radius 1.5
  circle A1 centre (0, 0) radius 3
  circle A2 centre (0, 0) radius 1.5
  circle A3 centre (0, 0) radius 3
  constraint concentric A0 A2
  constraint coincident A0.centre A1.centre
sketch "スケッチ3" plane through (0, 0, 0) normal (0, 1, 0) x (1, 0, 0)
  line L0 (0, -0.6) -> (0, -2)
  dimension "d5" = 1.4
  constraint vertical L0
  measures "d5" distance of L0.start L0.end
sketch "スケッチ4" plane through (0, 0, 0.6) normal (0, 0, 1) x (-1, 0, 0)
extrude "押し出し2" add sketch "スケッチ2" along normal blind 1.4
chamfer "面取り1" distance 1.4 angle 45 1 edges at (2.797, 1.0848, 2)

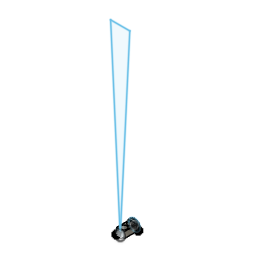
design "センサマウント"
Autodesk Fusion 360 part; units mm, degrees
sketch "スケッチ1" plane through (0, 0, 0) normal (0, 0, 1) x (1, 0, 0)
  line L0 (0, 0) -> (7.4, 0)
  line L1 (7.4, 0) -> (7.4, 14)
  line L2 (7.4, 14) -> (0, 14)
  line L3 (0, 14) -> (0, 0)
  line L4 (0, 0) -> (3.7, 0)
  line L5 (3.7, 0) -> (3.7, 14)
  line L6 (3.7, 0) -> (3.7, 3.6)
  circle A0 centre (3.7, 3.6) radius 2.85
  line L7 (3.7, 3.6) -> (3.7, 10.1)
  circle A1 centre (3.7, 10.1) radius 2.7
  dimension "d1" = 7.4
  dimension "d2" = 3.6
  dimension "d3" = 5.7
  dimension "d4" = 5.4
  dimension "d5" = 14
  dimension "d6" = 6.5
  constraint horizontal L0
  constraint vertical L1
  constraint horizontal L2
  constraint vertical L3
  constraint coincident L0.start L3.end
  constraint midpoint L0 L4.end
  constraint midpoint L2 L5.end
  constraint perpendicular L0 L6
  constraint coincident L6.end A0.centre
  constraint coincident L5 L7.end
  constraint coincident L7.end A1.centre
  measures "d1" distance of L0.start L0.end
  measures "d2" distance of L4.end L6.end
  measures "d3" diameter of A0
  measures "d4" diameter of A1
  measures "d5" distance of L4.end L5.end
  measures "d6" distance of L6.end L7.end
extrude "押し出し1" add sketch "スケッチ1" along normal blind 6 contours L0 L2 L3 L4 L5 L6 A0 L7 A1 | L0 L1 L2 L5 L6 A0 L7 A1
sketch "スケッチ2" plane through (0, 14, 0) normal (0, 1, 0) x (-1, 0, 0)
  line L0 (-7.4, 0) -> (0, 0)
  line L1 (0, 0) -> (0, 6)
  line L2 (0, 6) -> (-7.4, 6)
  line L3 (-7.4, 6) -> (-7.4, 0)
  line L4 (-7.4, 0) -> (-3.7, 0)
  line L5 (-3.7, 0) -> (-3.7, 3)
  circle A0 centre (-3.7, 3) radius 5.5
  line L6 (-7.4, 0) -> (-8.3098, 0)
  line L7 (0, 0) -> (0.9098, 0)
  dimension "d9" = 11
  constraint coincident L0.start L3.end
  constraint midpoint L0 L4.end
  constraint perpendicular L4 L5
  constraint coincident L5.end A0.centre
  constraint coincident A0 L6.end
  constraint perpendicular L3 L6
  constraint coincident L0.end L1.start
  constraint coincident A0 L7.end
  constraint perpendicular L1 L7
  measures "d9" diameter of A0
extrude "押し出し2" add sketch "スケッチ2" against normal blind 1 contours L1 L2 L3 A0 L6 L7
fillet "フィレット1" radius 1 2 edges at (0, 13, 3) (7.4, 13, 3)
sketch "スケッチ3" plane through (0, 14, 0) normal (0, 1, 0) x (-1, 0, 0)
  line L0 (-8.3098, 0) -> (0.9098, 0)
  arc A0 (0.9098, 0) -> (-8.3098, 0) centre (-3.7, 3) ccw
  line L1 (-8.3098, 0) -> (-3.7, 0)
  line L2 (-2.2, 6) -> (-5.2, 6)
  line L3 (-5.2, 6) -> (-5.2, 0)
  line L4 (-5.2, 0) -> (-2.2, 0)
  line L5 (-2.2, 0) -> (-2.2, 6)
  line L6 (-2.2, 6) -> (-5.2, 0) construction
  line L7 (-5.2, 6) -> (-2.2, 0) construction
  line L8 (-3.7, 0) -> (-3.7, 3)
  point P0 (-3.7, 3)
  dimension "d14" = 3
  dimension "d15" = 6
  dimension "d20" = 3
  constraint coincident L0.start A0.end
  constraint midpoint L0 L1.end
  constraint horizontal L2
  constraint perpendicular L2 L3
  constraint parallel L2 L4
  constraint parallel L3 L5
  constraint coincident L6 P0
  constraint coincident L7 P0
  constraint perpendicular L0 L8
  constraint coincident P0 A0.centre
  measures "d14" distance of L3.end L4.end
  measures "d15" distance of L2.end L3.end
  measures "d20" distance of L1.end P0
extrude "押し出し3" add sketch "スケッチ3" along normal blind 1.3 contours L0 L1 L2 L3 L4 L5
sketch "スケッチ4" plane through (0, 13, 0) normal (0, -1, 0) x (1, 0, 0)
  line L0 (-0.9098, 6) -> (8.3098, 6)
  arc A0 (8.3098, 6) -> (-0.9098, 6) centre (3.7, 3) ccw
sketch "スケッチ5" plane through (0, 0, 0) normal (0, -1, 0) x (1, 0, 0)
  line L0 (0, 0) -> (7.4, 0)
  line L1 (7.4, 0) -> (7.4, 6)
  line L2 (7.4, 6) -> (0, 6)
  line L3 (0, 6) -> (0, 0)
  line L4 (0, 0) -> (3.7, 0)
  line L5 (3.7, 0) -> (3.7, 2.4)
  line L6 (3.7, 0) -> (13.1205, 179.7533)
  line L7 (3.7, 0) -> (-5.7205, 179.7533)
  line L8 (-5.7205, 179.7533) -> (13.1205, 179.7533)
  dimension "d19" = 180
  constraint coincident L0.start L3.end
  constraint midpoint L0 L4.end
  constraint perpendicular L4 L5
  constraint symmetric L4.end L5 L6.start
  constraint symmetric L5 L6.end L7.end
  measures "d19" distance of L4.end L6.end
sketch "スケッチ6" plane through (0, 0, 0) normal (0, -1, 0) x (1, 0, 0)
  line L0 (4, 0) -> (4, 1)
  constraint vertical L0

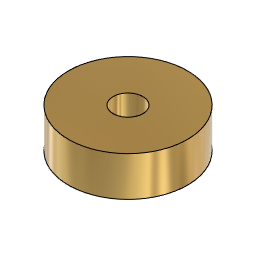
design "歯車M0.3T20(仮)"
Autodesk Fusion 360 part; units mm, degrees
sketch "スケッチ1" plane through (0, 0, 0) normal (0, 0, 1) x (1, 0, 0)
  circle A0 centre (0, 0) radius 0.75
  circle A1 centre (0, 0) radius 3
  dimension "d1" = 1.5
  dimension "d2" = 6
  constraint coincident A0.centre A1.centre
  measures "d1" diameter of A0
  measures "d2" diameter of A1
extrude "押し出し1" add sketch "スケッチ1" along normal blind 2

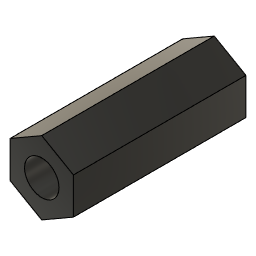
design "スペーサーM3 15"
Autodesk Fusion 360 part; units mm, degrees
sketch "スケッチ1" plane through (0, 0, 0) normal (0, 1, 0) x (1, 0, 0)
  line L0 (0, 0) -> (5.5, 0)
  line L1 (0, 0) -> (2.75, 0)
  circle A0 centre (2.75, 0) radius 1.5
  line L2 (2.75, 0) -> (4.125, 2.3816)
  line L3 (2.75, 0) -> (5.5, 0) construction
  line L4 (2.75, 0) -> (1.375, 2.3816)
  line L5 (2.75, 0) -> (0, 0)
  line L6 (2.75, 0) -> (1.375, -2.3816)
  line L7 (2.75, 0) -> (4.125, -2.3816)
  line L8 (2.75, 0) -> (5.5, 0)
  line L9 (5.5, 0) -> (5.5, -2.7859)
  line L10 (5.5, -2.7859) -> (5.5, 2.5)
  line L11 (6.5377, 0.9886) -> (1.9599, 3.6316)
  line L12 (3.7877, 3.7745) -> (-0.7901, 1.1316)
  line L13 (0, 2.7859) -> (0, -2.5)
  line L14 (-1.0377, -0.9886) -> (3.5401, -3.6316)
  line L15 (1.7123, -3.7745) -> (6.2901, -1.1316)
  dimension "d1" = 5.5
  dimension "d2" = 3
  dimension "d3" = 2.75
  dimension "d4" = 60
  dimension "d6" = 360
  dimension "d8" = 360
  constraint coincident L0.start L1.start
  constraint horizontal L0
  constraint midpoint L0 L1.end
  constraint coincident L1.end A0.centre
  constraint horizontal L3
  constraint perpendicular L3 L9
  constraint perpendicular L8 L10
  measures "d1" distance of L0.start L0.end
  measures "d2" diameter of A0
  measures "d3" distance of L1.end L2.end
  measures "d4" angle of L2 L3
extrude "押し出し1" add sketch "スケッチ1" along normal blind 15 contours L0 A0 L2 L8 L10 L11 | L0 A0 L7 L8 L9 L10 L15 | L0 L1 A0 L5 L6 L13 L14 | L0 L1 A0 L4 L5 L12 L13 | A0 L2 L4 L11 L12 | A0 L6 L7 L14 L15

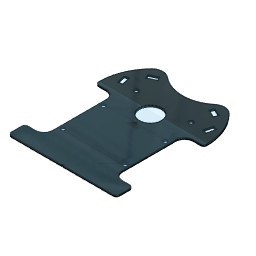
design "メイン基板"
Autodesk Fusion 360 part; units mm, degrees
sketch "スケッチ1" plane through (0, 0, 0) normal (0, 0, 1) x (1, 0, 0)
  line L0 (0, 0) -> (-46.8, 0)
  line L1 (-46.8, 0) -> (-46.8, 44)
  line L2 (-46.8, 44) -> (0, 44)
  line L3 (0, 44) -> (0, 0)
  dimension "d1" = 46.8
  dimension "d4" = 44
  constraint horizontal L0
  constraint vertical L1
  constraint horizontal L2
  constraint vertical L3
  constraint coincident L0.start L3.end
  measures "d1" distance of L0.start L0.end
  measures "d4" distance of L0.start L2.end
extrude "押し出し1" add sketch "スケッチ1" along normal blind 1 makes body 1
sketch "スケッチ4" plane through (0, 0, 1) normal (0, 0, 1) x (-1, 0, 0)
  line L0 (0, -44) -> (46.8, -44)
  line L1 (46.8, -44) -> (46.8, 0)
  line L2 (46.8, 0) -> (0, 0)
  line L3 (0, 0) -> (0, -44)
  line L4 (0, 0) -> (2.5, 0)
  line L5 (2.5, 0) -> (2.5, -4.4)
  circle A0 centre (2.5, -4.4) radius 1.5
  line L6 (2.5, -4.4) -> (2.5, -31.6)
  line L7 (46.8, 0) -> (23.4, 0)
  line L8 (23.4, 0) -> (23.4, -44)
  circle A1 centre (2.5, -31.6) radius 1.5
  line L9 (2.5, -4.4) -> (2.5, -18)
  line L10 (4.5787, -18) -> (2.5, -18)
  line L11 (2.5, 0) -> (2.5, -1.2)
  line L12 (2.5, -1.2) -> (1, -1.2)
  line L13 (1, -1.2) -> (1, -2.2)
  line L14 (1, -2.2) -> (4, -2.2)
  line L15 (4, -2.2) -> (4, -1.2)
  line L16 (4, -1.2) -> (2.5, -1.2)
  line L17 (2.5, 0) -> (2.5, -9)
  line L18 (2.5, -9) -> (2, -9)
  line L19 (2, -9) -> (2, -14)
  line L20 (2, -14) -> (3, -14)
  line L21 (3, -14) -> (3, -9)
  line L22 (3, -9) -> (2.5, -9)
  line L23 (2, -27) -> (2, -22)
  line L24 (3, -22) -> (3, -27)
  line L25 (2, -22) -> (3, -22)
  line L26 (3, -27) -> (2.5, -27)
  line L27 (2.5, -27) -> (2, -27)
  line L28 (2.5, -34.8) -> (1, -34.8)
  line L29 (4, -34.8) -> (2.5, -34.8)
  line L30 (4, -33.8) -> (4, -34.8)
  line L31 (1, -33.8) -> (4, -33.8)
  line L32 (1, -34.8) -> (1, -33.8)
  line L33 (42.8, -33.8) -> (42.8, -34.8)
  line L34 (42.8, -34.8) -> (44.3, -34.8)
  line L35 (44.3, -34.8) -> (45.8, -34.8)
  line L36 (45.8, -34.8) -> (45.8, -33.8)
  line L37 (45.8, -33.8) -> (42.8, -33.8)
  circle A2 centre (44.3, -31.6) radius 1.5
  line L38 (43.8, -27) -> (44.3, -27)
  line L39 (43.8, -22) -> (43.8, -27)
  line L40 (44.3, -27) -> (44.8, -27)
  line L41 (44.8, -27) -> (44.8, -22)
  line L42 (44.8, -22) -> (43.8, -22)
  line L43 (44.8, -14) -> (43.8, -14)
  line L44 (43.8, -14) -> (43.8, -9)
  line L45 (44.8, -9) -> (44.8, -14)
  line L46 (44.3, -9) -> (44.8, -9)
  line L47 (43.8, -9) -> (44.3, -9)
  circle A3 centre (44.3, -4.4) radius 1.5
  line L48 (45.8, -2.2) -> (42.8, -2.2)
  line L49 (42.8, -2.2) -> (42.8, -1.2)
  line L50 (42.8, -1.2) -> (44.3, -1.2)
  line L51 (44.3, -1.2) -> (45.8, -1.2)
  line L52 (45.8, -1.2) -> (45.8, -2.2)
  dimension "d6" = 2.5
  dimension "d7" = 4.4
  dimension "d8" = 3
  dimension "d9" = 27.2
  dimension "d10" = 3
  dimension "d11" = 1.2
  dimension "d12" = 9
  dimension "d13" = 5
  dimension "d14" = 0.5
  constraint coincident L2.end L3.start
  constraint perpendicular L3 L4
  constraint perpendicular L2 L5
  constraint coincident L5.end A0.centre
  constraint parallel L5 L6
  constraint coincident L1.end L2.start
  constraint midpoint L2 L7.end
  constraint midpoint L0 L8.end
  constraint coincident L6.end A1.centre
  constraint midpoint L6 L9.end
  constraint perpendicular L6 L10
  constraint perpendicular L4 L11
  constraint perpendicular L11 L12
  constraint perpendicular L12 L13
  constraint perpendicular L5 L14
  constraint perpendicular L14 L15
  constraint perpendicular L11 L16
  constraint perpendicular L4 L17
  constraint perpendicular L9 L18
  constraint perpendicular L18 L19
  constraint perpendicular L9 L20
  constraint perpendicular L20 L21
  constraint symmetric L10 L11.end L28.start
  constraint symmetric L10 L12.end L28.end
  constraint symmetric L10 L13.end L31.start
  constraint symmetric L10 L14.end L30.start
  constraint symmetric L10 L15.end L29.start
  constraint symmetric L10 L17.end L26.end
  constraint symmetric L10 L18.end L23.start
  constraint symmetric L10 L19.end L23.end
  constraint symmetric L10 L20.end L24.start
  constraint symmetric L10 L21.end L24.end
  constraint symmetric A0 L8 A3
  constraint symmetric L8 A1 A2
  constraint symmetric L8 L11.end L50.end
  constraint symmetric L8 L12.end L51.end
  constraint symmetric L8 L13.end L48.start
  constraint symmetric L8 L14.end L48.end
  constraint symmetric L8 L15.end L49.end
  constraint symmetric L8 L17.end L46.start
  constraint symmetric L8 L18.end L45.start
  constraint symmetric L8 L19.end L43.start
  constraint symmetric L8 L20.end L43.end
  constraint symmetric L8 L21.end L44.end
  constraint symmetric L8 L23.start L40.end
  constraint symmetric L8 L23.end L41.end
  constraint symmetric L8 L24.start L39.start
  constraint symmetric L8 L24.end L38.start
  constraint symmetric L8 L26.end L38.end
  constraint symmetric L8 L28.start L34.end
  constraint symmetric L8 L28.end L35.end
  constraint symmetric L8 L29.start L33.end
  constraint symmetric L8 L30.start L33.start
  constraint symmetric L8 L31.start L36.end
  measures "d6" distance of L2.end L4.end
  measures "d7" distance of L4.end L5.end
  measures "d8" diameter of A0
  measures "d9" distance of L5.end L6.end
  measures "d10" diameter of A1
  measures "d11" distance of L4.end L11.end
  measures "d12" distance of L4.end L17.end
  measures "d13" distance of L18.end L19.end
  measures "d14" distance of L17.end L18.end
extrude "押し出し2" cut sketch "スケッチ4" against normal blind 1 contours L5 A0 L6 L9 L17 | L5 A0 L6 L9 L17 | A1 | A2 | A3 bodies 1
sketch "スケッチ5" plane through (0, 0, 1) normal (0, 0, 1) x (-1, 0, 0)
  circle A0 centre (44.3, -31.6) radius 1.5
  circle A1 centre (2.5, -31.6) radius 1.5
  circle A2 centre (44.3, -4.4) radius 1.5
  circle A3 centre (2.5, -4.4) radius 1.5
  line L0 (0, -44) -> (46.8, -44)
  line L1 (46.8, -44) -> (46.8, 0)
  line L2 (46.8, 0) -> (0, 0)
  line L3 (0, 0) -> (0, -44)
  line L4 (0, 0) -> (0, 12)
  line L5 (0, 12) -> (23.4, 12)
  line L6 (23.4, 12) -> (23.4, 0)
  line L7 (0, 12) -> (-13, 12)
  line L8 (0, 12) -> (0, 6)
  line L9 (-13, 12) -> (-13, 6)
  line L10 (-13, 6) -> (0, 6)
  line L11 (46.8, 12) -> (23.4, 12)
  line L12 (46.8, 0) -> (46.8, 12)
  line L13 (59.8, 6) -> (46.8, 6)
  line L14 (46.8, 12) -> (59.8, 12)
  line L15 (59.8, 12) -> (59.8, 6)
  line L16 (45.8, -1.2) -> (45.8, -34.8)
  line L17 (45.8, -34.8) -> (45.8, -18)
  line L18 (45.8, -18) -> (43, -18)
  line L19 (46.8, -36) -> (46.8, -48)
  line L20 (59.8, -42) -> (46.8, -42)
  line L21 (59.8, -48) -> (59.8, -42)
  line L22 (46.8, -48) -> (59.8, -48)
  line L23 (46.8, -48) -> (23.4, -48)
  line L24 (0, -48) -> (23.4, -48)
  line L25 (0, -48) -> (-13, -48)
  line L26 (-13, -48) -> (-13, -42)
  line L27 (-13, -42) -> (0, -42)
  line L28 (0, -36) -> (0, -48)
  line L29 (46.8, -44) -> (59.8, -44)
  line L30 (59.8, -44) -> (-13, -44)
  dimension "d17" = 13
  dimension "d20" = 12
  constraint coincident L2.end L3.start
  constraint perpendicular L2 L4
  constraint perpendicular L1 L5
  constraint midpoint L2 L6.end
  constraint perpendicular L2 L6
  constraint perpendicular L4 L7
  constraint midpoint L4 L8.end
  constraint perpendicular L7 L9
  constraint perpendicular L4 L10
  constraint symmetric L2.end L6 L1.end
  constraint symmetric L4.end L6 L11.start
  constraint symmetric L5.end L6 L11.end
  constraint symmetric L6 L7.end L14.end
  constraint symmetric L6 L8.end L13.end
  constraint symmetric L6 L9.end L13.start
  constraint midpoint L16 L17.end
  constraint perpendicular L16 L18
  constraint symmetric L2.end L18 L28.start
  constraint symmetric L4.end L18 L24.start
  constraint symmetric L5.end L18 L23.end
  constraint symmetric L7.end L18 L25.end
  constraint symmetric L8.end L18 L27.end
  constraint symmetric L9.end L18 L26.end
  constraint symmetric L11.start L18 L19.end
  constraint symmetric L1.end L18 L19.start
  constraint symmetric L13.start L18 L20.start
  constraint symmetric L13.end L18 L20.end
  constraint symmetric L14.end L18 L21.start
  constraint coincident L0.end L1.start
  constraint coincident L21 L29.end
  constraint perpendicular L21 L29
  constraint coincident L26 L30.end
  constraint perpendicular L26 L30
  measures "d17" distance of L4.end L7.end
  measures "d20" distance of L2.end L4.end
extrude "押し出し3" add sketch "スケッチ5" against normal blind 1 contours L3 L26 L27 L28 L30 | L1 L19 L20 L21 L29 L30 | L2 L4 L5 L6 L8 | L2 L6 L11 L12 | L4 L7 L8 L9 L10 | L12 L13 L14 L15 bodies 1
fillet "フィレット1" radius 6 2 edges at (0, -6, 0.5) (-46.8, -6, 0.5) on bodies 1
fillet "フィレット2" radius 6 2 edges at (0, 42, 0.5) (-46.8, 42, 0.5) on bodies 1
sketch "スケッチ8" plane through (0, 0, 1) normal (0, 0, 1) x (-1, 0, 0)
  line L0 (-13, 12) -> (-13, 6)
  line L1 (-13, 6) -> (-6, 6)
  arc A0 (0, 0) -> (-6, 6) centre (-6, 0) ccw
  line L2 (0, 0) -> (0, -36)
  arc A1 (-6, -42) -> (0, -36) centre (-6, -36) ccw
  line L3 (-6, -42) -> (-13, -42)
  line L4 (-13, -42) -> (-13, -44)
  line L5 (59.8, -44) -> (59.8, -42)
  line L6 (59.8, -42) -> (52.8, -42)
  arc A2 (46.8, -36) -> (52.8, -42) centre (52.8, -36) ccw
  line L7 (46.8, -36) -> (46.8, 0)
  arc A3 (52.8, 6) -> (46.8, 0) centre (52.8, 0) ccw
  line L8 (52.8, 6) -> (59.8, 6)
  line L9 (59.8, 6) -> (59.8, 12)
  line L10 (59.8, 12) -> (-13, 12)
  circle A4 centre (44.3, -31.6) radius 1.5
  circle A5 centre (2.5, -31.6) radius 1.5
  circle A6 centre (44.3, -4.4) radius 1.5
  circle A7 centre (2.5, -4.4) radius 1.5
  line L11 (23.4, 11.134) -> (23.4, -48)
  line L12 (44.8, -14) -> (44.8, -22)
  line L13 (44.8, -18) -> (23.4, -18)
  line L14 (-13, -44) -> (59.8, -44)
  constraint midpoint L12 L13.start
  constraint coincident L11 L13.end
  constraint perpendicular L11 L13